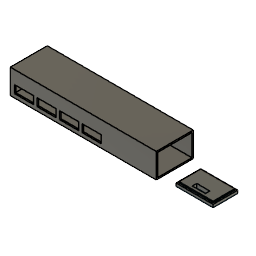
CraftHUB (Autodesk Fusion 360 design; units mm, degrees)
part number: 2026-11-08-10-42-45-729
Autodesk Fusion 360 part; units mm, degrees
sketch "Skizze1" plane through (0, 0, 0) normal (0, 0, 1) x (1, 0, 0)
  line L0 (0, 0) -> (87.4563, 0)
  line L1 (87.4563, 0) -> (87.4563, 25.5)
  line L2 (87.4563, 25.5) -> (0, 25.5)
  line L3 (0, 25.5) -> (0, 0)
  dimension "d1" = 25.5
  constraint horizontal L0
  constraint vertical L1
  constraint horizontal L2
  constraint vertical L3
  constraint coincident L0.start L3.end
  measures "d1" distance of L0.start L2.end
extrude "Extrusion1" add sketch "Skizze1" along normal blind 2 makes body 1
extrude "Extrusion2" add 1 faces at (29.1521, 0, 0.6667) along direction (0, -1, 0) blind 16 on bodies 1 bodies 1
extrude "Extrusion3" add 1 faces at (29.1521, 11.6667, 2) along direction (0, 0, 1) blind 20 on bodies 1 bodies 1
extrude "Extrusion4" cut 1 faces at (29.1521, -16, 14.6667) along direction (0, 1, 0) blind 16 on bodies 1 bodies 1
extrude "Extrusion5" cut 1 faces at (29.1521, 17, 22) along direction (0, 0, -1) blind 5 on bodies 1 bodies 1
shell "Schale1" thickness 1 removed faces 1 at (87.4563, 8.5, 5.6667) on bodies 1
sketch "Skizze2" plane through (0, 0, 0) normal (0, 1, 0) x (1, 0, 0)
move_body "Verschieben1" bodies 1 to x (1, 0, 0) y (0, 1, 0) z (0, 0, 1) at (0, 55, 0)
sketch "Skizze3" plane through (0, 0, 0) normal (0, 0, 1) x (1, 0, 0)
  line L0 (0, 0) -> (25, 0)
  line L1 (25, 0) -> (25, 15)
  line L2 (25, 15) -> (0, 15)
  line L3 (0, 15) -> (0, 0)
  constraint horizontal L0
  constraint vertical L1
  constraint horizontal L2
  constraint vertical L3
  constraint coincident L0.start L3.end
extrude "Extrusion6" add sketch "Skizze3" along normal blind 1 separate body makes body 2
move_body "Verschieben2" bodies 2 to x (0, -1, 0) y (0, 0, -1) z (1, 0, 0) at (12, 93.9284, 5.8432)
move_body "Verschieben3" bodies 2 to x (1, 0, 0) y (0, 1, 0) z (0, 0, 1) at (60, -25, 0)
sketch "Skizze4" plane through (73, 0, 0) normal (1, 0, 0) x (0, 1, 0)
move_body "Verschieben4" bodies 2 to x (1, 0, 0) y (0, 1, 0) z (0, 0, 1) at (0, -31, 0)
move_body "Verschieben5" bodies 2 to x (1, 0, 0) y (0, 1, 0) z (0, 0, 1) at (16, 42, 10)
extrude "Extrusion7" cut 1 faces at (88.3333, 54.9284, 10.8432) along direction (0, 1, 0) blind 1.5 on bodies 2 bodies 2
move_body "Verschieben6" bodies 2 to x (1, 0, 0) y (0, 1, 0) z (0, 0, 1) at (0, 33, 0)
sketch "Skizze5" plane through (0, 0, 0) normal (0, 0, 1) x (1, 0, 0)
  line L0 (0, 0) -> (25.4884, 0)
  line L1 (25.4884, 0) -> (25.4884, 17.0037)
  line L2 (25.4884, 17.0037) -> (0, 17.0037)
  line L3 (0, 17.0037) -> (0, 0)
  constraint horizontal L0
  constraint vertical L1
  constraint horizontal L2
  constraint vertical L3
  constraint coincident L0.start L3.end
extrude "Extrusion8" add sketch "Skizze5" along normal blind 2 separate body makes body 3
move_body "Verschieben7" bodies 2 to x (0, 0, -1) y (-1, 0, 0) z (0, 1, 0) at (113.2137, -2.6294, 89.8432)
move_body "Verschieben8" bodies 2 to x (1, 0, 0) y (0, 1, 0) z (0, 0, 1) at (0, 3, 1)
move_body "Verschieben9" bodies 2 to x (1, 0, 0) y (0, 1, 0) z (0, 0, 1) at (0.7, 0, 0)
move_body "Verschieben10" bodies 2 to x (1, 0, 0) y (0, 1, 0) z (0, 0, 1) at (0, 0.2, 0)
move_body "Verschieben11" bodies 2 to x (1, 0, 0) y (0, 1, 0) z (0, 0, 1) at (0, -0.4, 0)
move_body "Verschieben12" bodies 2 to x (1, 0, 0) y (0, 1, 0) z (0, 0, 1) at (0, -0.1, 0)
move_body "Verschieben13" bodies 2 to x (1, 0, 0) y (0, 1, 0) z (0, 0, 1) at (0, 0.05, 0)
move_body "Verschieben14" bodies 2 to x (1, 0, 0) y (0, 1, 0) z (0, 0, 1) at (0, 0.025, 0)
move_body "Verschieben15" bodies 2 to x (1, 0, 0) y (0, 1, 0) z (0, 0, 1) at (0, 0.025, 0)
move_body "Verschieben16" bodies 2 to x (1, 0, 0) y (0, 1, 0) z (0, 0, 1) at (0, 0.1, 0)
move_body "Verschieben17" bodies 2 to x (1, 0, 0) y (0, 1, 0) z (0, 0, 1) at (0, -0.075, 0)
move_body "Verschieben18" bodies 2 to x (1, 0, 0) y (0, 1, 0) z (0, 0, 1) at (0, -0.05, 0)
move_body "Verschieben19" bodies 2 to x (1, 0, 0) y (0, 1, 0) z (0, 0, 1) at (0, -0.01, 0)
move_body "Verschieben20" bodies 2 to x (1, 0, 0) y (0, 1, 0) z (0, 0, 1) at (0, 0.006, 0)
move_body "Verschieben21" bodies 2 to x (1, 0, 0) y (0, 1, 0) z (0, 0, 1) at (0, 0.06, 0)
move_body "Verschieben22" bodies 2 to x (1, 0, 0) y (0, 1, 0) z (0, 0, 1) at (0, -0.03, 0)
move_body "Verschieben23" bodies 2 to x (1, 0, 0) y (0, 1, 0) z (0, 0, 1) at (0.005, 0, 0)
combine "Kombinieren1" operation add target body 2 tool bodies 3
move_body "Verschieben24" bodies 2 to x (1, 0, 0) y (0, 1, 0) z (0, 0, 1) at (90, 110, 0)
sketch "Skizze6" plane through (0, 0, 0) normal (0, 0, 1) x (1, 0, 0)
  line L0 (0, 0) -> (13.0982, 0)
  line L1 (13.0982, 0) -> (13.0982, 5.3)
  line L2 (13.0982, 5.3) -> (0, 5.3)
  line L3 (0, 5.3) -> (0, 0)
  dimension "d19" = 5.3
  constraint horizontal L0
  constraint vertical L1
  constraint horizontal L2
  constraint vertical L3
  constraint coincident L0.start L3.end
  measures "d19" distance of L0.start L2.end
extrude "Extrusion9" add sketch "Skizze6" along normal blind 2 separate body makes body 4
move_body "Verschieben25" bodies 4 to x (1, 0, 0) y (0, 0, -1) z (0, 1, 0) at (60.7638, 54.3022, 10.0071)
move_body "Verschieben26" bodies 4 to x (1, 0, 0) y (0, 1, 0) z (0, 0, 1) at (-57, 0, 0)
move_face "Fläche verschieben1" by (-0.7, 0, 0) 1 faces at (8.1299, 54.3022, 6.4738) on bodies 4
move_body "Verschieben27" bodies 4 to x (1, 0, 0) y (0, 1, 0) z (0, 0, 1) at (-0.8, 0, 0)
copy_body "Körper kopieren/einfügen1" bodies 4 makes body 5
move_body "Verschieben28" bodies 5 to x (1, 0, 0) y (0, 1, 0) z (0, 0, 1) at (15.5, 0, 0)
copy_body "Körper kopieren/einfügen2" bodies 5 makes body 6
move_body "Verschieben29" bodies 6 to x (1, 0, 0) y (0, 1, 0) z (0, 0, 1) at (15.5, 0, 0)
copy_body "Körper kopieren/einfügen3" bodies 6 makes body 7
move_body "Verschieben30" bodies 7 to x (1, 0, 0) y (0, 1, 0) z (0, 0, 1) at (15.5, 0, 0)
extrude "Extrusion10" add 1 faces at (87.4563, 71.6667, 16.6667) along direction (1, 0, 0) blind 12 on bodies 1 bodies 1
extrude "Extrusion11" add 1 faces at (99.4563, 71.6667, 16.6667) along direction (1, 0, 0) blind 1 on bodies 1 bodies 1
move_body "Verschieben31" bodies 7 4 5 6 to x (1, 0, 0) y (0, 1, 0) z (0, 0, 1) at (0, 0, -2)
combine "Kombinieren2" operation cut target body 1 tool bodies 4 5 6 7
move_body "Verschieben32" bodies 2 to x (1, 0, 0) y (0, 1, 0) z (0, 0, 1) at (21, -52, 0)
move_body "Verschieben33" bodies 2 1 to x (1, 0, 0) y (0, 1, 0) z (0, 0, 1) at (0, -55, 0)
move_body "Verschieben34" bodies 2 1 to x (1, 0, 0) y (0, 1, 0) z (0, 0, 1) at (0, 74, 0)
sketch "Skizze7" plane through (0, 0, 0) normal (0, 0, 1) x (1, 0, 0)
  line L0 (0, 0) -> (9, 0)
  line L1 (9, 0) -> (9, 3)
  line L2 (9, 3) -> (0, 3)
  line L3 (0, 3) -> (0, 0)
  constraint horizontal L0
  constraint vertical L1
  constraint horizontal L2
  constraint vertical L3
  constraint coincident L0.start L3.end
extrude "Extrusion12" add sketch "Skizze7" along normal blind 2 separate body makes body 8
move_body "Verschieben35" bodies 8 to x (1, 0, 0) y (0, 1, 0) z (0, 0, 1) at (116, 67, 0)
extrude "Extrusion13" add 1 faces at (119, 69, 2) along direction (0, 0, 1) blind 4 on bodies 8 bodies 8
move_body "Verschieben36" bodies 8 to x (1, 0, 0) y (0, 1, 0) z (0, 0, 1) at (5, 13, 0)
move_body "Verschieben37" bodies 8 to x (1, 0, 0) y (0, 1, 0) z (0, 0, 1) at (-1.5, 0, 0)
move_body "Verschieben38" bodies 8 to x (1, 0, 0) y (0, 1, 0) z (0, 0, 1) at (-0.5, 0, 0)
move_body "Verschieben39" bodies 8 to x (1, 0, 0) y (0, 1, 0) z (0, 0, 1) at (0.26, 0, 0)
combine "Kombinieren3" operation cut target body 2 tool bodies 8
sketch "Skizze8" plane through (0, 0, 0) normal (0, 0, -1) x (1, 0, 0)
  line L0 (128.26, -83) -> (119.26, -83)
  line L1 (119.26, -83) -> (119.26, -80)
  line L2 (119.26, -80) -> (128.26, -80)
  line L3 (128.26, -80) -> (128.26, -83)
  line L4 (111, -77) -> (111, -94.0037)
  line L5 (111, -94.0037) -> (136.4884, -94.0037)
  line L6 (136.4884, -94.0037) -> (136.4884, -77)
  line L7 (136.4884, -77) -> (111, -77)
sketch "Skizze9" plane through (0, 0, 0) normal (0, 0, -1) x (1, 0, 0)
  line L0 (128, -91) -> (119, -91) construction
  line L1 (119, -91) -> (119, -93) construction
  line L2 (119, -93) -> (128, -93) construction
  line L3 (128, -93) -> (128, -91) construction
  dimension "d30" = 0.5
  dimension "d31" = 0
  text T0 "Philipp Buda 8.11.2026 " font "Arial" height 0.5 align centre top in box 9 x 2 at (128, -91) x (-1, 0) y (0, -1) spacing 1 kerned
extrude "Extrusion14" add sketch "Skizze9" along normal blind 0.0111 text T0 bodies 2
equation "d31 = 'Philipp Buda 8.11.2026 '"
